Untitled (shOT3eEF) (Autodesk Fusion 360 design; units mm, degrees)
Autodesk Fusion 360 part; units mm, degrees
sketch "Sketch1" plane through (0, 0, 0) normal (0, 0, 1) x (1, 0, 0)
  line L0 (-6.3093, 9.3027) -> (-6.3093, 5.8366)
  line L1 (-6.7958, 5.7043) -> (-9.574, 5.7043)
  line L2 (-9.574, 5.7043) -> (-9.574, 5.8366)
  line L3 (-6.7958, 5.7043) -> (-6.7958, 5.8366)
  line L4 (-6.7958, 5.8366) -> (-6.3093, 5.8366)
  line L5 (-10.0605, 5.8366) -> (-10.0605, 9.3024)
  line L6 (-9.574, 5.8366) -> (-10.0605, 5.8366)
  line L7 (-10.0605, 9.3024) -> (-9.574, 9.3024)
  line L8 (-9.574, 9.3024) -> (-9.574, 9.4347)
  line L9 (-9.574, 9.4347) -> (-6.7958, 9.4347)
  line L10 (-6.7958, 9.4347) -> (-6.7958, 9.3024)
  line L11 (-6.7958, 9.3024) -> (-6.3093, 9.3024)
  line L12 (-6.7958, 5.8366) -> (-6.3093, 5.8366)
  line L13 (-6.7958, 5.7043) -> (-9.574, 5.7043)
  line L14 (-9.574, 5.8366) -> (-10.0605, 5.8366)
  line L15 (-9.574, 5.7043) -> (-9.574, 5.8366)
  line L16 (-6.7958, 5.7043) -> (-6.7958, 5.8366)
  line L17 (-6.3093, 9.3027) -> (-6.3093, 5.8366)
  line L18 (-6.7958, 9.4347) -> (-6.7958, 9.3024)
  line L19 (-9.574, 9.3024) -> (-9.574, 9.4347)
  line L20 (-10.0605, 5.8366) -> (-10.0605, 9.3024)
  line L21 (-6.7958, 9.3024) -> (-6.3093, 9.3024)
  line L22 (-9.574, 9.4347) -> (-6.7958, 9.4347)
  line L23 (-10.0605, 9.3024) -> (-9.574, 9.3024)
  line L24 (-1.5571, 5.7043) -> (-1.5571, 5.8366)
  line L25 (-4.3352, 5.7043) -> (-4.3352, 5.8366)
  line L26 (-1.5571, 9.4347) -> (-1.5571, 9.3024)
  line L27 (-4.3352, 9.3024) -> (-4.3352, 9.4347)
  line L28 (-4.3352, 5.8366) -> (-4.8218, 5.8366)
  line L29 (-4.8218, 9.3024) -> (-4.3352, 9.3024)
  line L30 (-1.5571, 5.8366) -> (-1.0705, 5.8366)
  line L31 (-4.8218, 9.3024) -> (-4.3352, 9.3024)
  line L32 (-1.5571, 5.7043) -> (-4.3352, 5.7043)
  line L33 (-1.5571, 5.8366) -> (-1.0705, 5.8366)
  line L34 (-1.5571, 5.7043) -> (-1.5571, 5.8366)
  line L35 (-4.3352, 5.8366) -> (-4.8218, 5.8366)
  line L36 (-4.3352, 9.4347) -> (-1.5571, 9.4347)
  line L37 (-1.5571, 5.7043) -> (-4.3352, 5.7043)
  line L38 (-4.3352, 9.4347) -> (-1.5571, 9.4347)
  line L39 (-1.5571, 9.3024) -> (-1.0705, 9.3024)
  line L40 (-1.5571, 9.3024) -> (-1.0705, 9.3024)
  line L41 (-4.3352, 9.3024) -> (-4.3352, 9.4347)
  line L42 (-1.5571, 9.4347) -> (-1.5571, 9.3024)
  line L43 (-4.3352, 5.7043) -> (-4.3352, 5.8366)
  line L44 (-1.0705, 9.3027) -> (-1.0705, 5.8366)
  line L45 (-1.0705, 9.3027) -> (-1.0705, 5.8366)
  line L46 (-4.8218, 5.8366) -> (-4.8218, 9.3024)
  line L47 (-4.8218, 5.8366) -> (-4.8218, 9.3024)
  line L48 (3.6817, 5.7043) -> (3.6817, 5.8366)
  line L49 (0.9035, 5.7043) -> (0.9035, 5.8366)
  line L50 (3.6817, 9.4347) -> (3.6817, 9.3024)
  line L51 (0.9035, 9.3024) -> (0.9035, 9.4347)
  line L52 (0.9035, 5.8366) -> (0.417, 5.8366)
  line L53 (0.417, 9.3024) -> (0.9035, 9.3024)
  line L54 (3.6817, 5.8366) -> (4.1682, 5.8366)
  line L55 (0.417, 9.3024) -> (0.9035, 9.3024)
  line L56 (3.6817, 5.7043) -> (0.9035, 5.7043)
  line L57 (3.6817, 5.8366) -> (4.1682, 5.8366)
  line L58 (3.6817, 5.7043) -> (3.6817, 5.8366)
  line L59 (0.9035, 5.8366) -> (0.417, 5.8366)
  line L60 (0.9035, 9.4347) -> (3.6817, 9.4347)
  line L61 (3.6817, 5.7043) -> (0.9035, 5.7043)
  line L62 (0.9035, 9.4347) -> (3.6817, 9.4347)
  line L63 (3.6817, 9.3024) -> (4.1682, 9.3024)
  line L64 (3.6817, 9.3024) -> (4.1682, 9.3024)
  line L65 (0.9035, 9.3024) -> (0.9035, 9.4347)
  line L66 (3.6817, 9.4347) -> (3.6817, 9.3024)
  line L67 (0.9035, 5.7043) -> (0.9035, 5.8366)
  line L68 (4.1682, 9.3027) -> (4.1682, 5.8366)
  line L69 (4.1682, 9.3027) -> (4.1682, 5.8366)
  line L70 (0.417, 5.8366) -> (0.417, 9.3024)
  line L71 (0.417, 5.8366) -> (0.417, 9.3024)
  line L72 (8.9204, 5.7043) -> (8.9204, 5.8366)
  line L73 (6.1423, 5.7043) -> (6.1423, 5.8366)
  line L74 (8.9204, 9.4347) -> (8.9204, 9.3024)
  line L75 (6.1423, 9.3024) -> (6.1423, 9.4347)
  line L76 (6.1423, 5.8366) -> (5.6557, 5.8366)
  line L77 (5.6557, 9.3024) -> (6.1423, 9.3024)
  line L78 (8.9204, 5.8366) -> (9.407, 5.8366)
  line L79 (5.6557, 9.3024) -> (6.1423, 9.3024)
  line L80 (8.9204, 5.7043) -> (6.1423, 5.7043)
  line L81 (8.9204, 5.8366) -> (9.407, 5.8366)
  line L82 (8.9204, 5.7043) -> (8.9204, 5.8366)
  line L83 (6.1423, 5.8366) -> (5.6557, 5.8366)
  line L84 (6.1423, 9.4347) -> (8.9204, 9.4347)
  line L85 (8.9204, 5.7043) -> (6.1423, 5.7043)
  line L86 (6.1423, 9.4347) -> (8.9204, 9.4347)
  line L87 (8.9204, 9.3024) -> (9.407, 9.3024)
  line L88 (8.9204, 9.3024) -> (9.407, 9.3024)
  line L89 (6.1423, 9.3024) -> (6.1423, 9.4347)
  line L90 (8.9204, 9.4347) -> (8.9204, 9.3024)
  line L91 (6.1423, 5.7043) -> (6.1423, 5.8366)
  line L92 (9.407, 9.3027) -> (9.407, 5.8366)
  line L93 (9.407, 9.3027) -> (9.407, 5.8366)
  line L94 (5.6557, 5.8366) -> (5.6557, 9.3024)
  line L95 (5.6557, 5.8366) -> (5.6557, 9.3024)
  line L96 (-9.574, 4.0636) -> (-9.574, 4.1959)
  line L97 (5.6557, 0.5981) -> (5.6557, 4.0636)
  line L98 (4.1682, 4.0636) -> (4.1682, 0.5981)
  line L99 (5.6557, 0.5981) -> (5.6557, 4.0636)
  line L100 (-9.574, 4.0636) -> (-9.574, 4.1959)
  line L101 (8.9204, 0.4658) -> (8.9204, 0.5981)
  line L102 (-10.0605, 4.0636) -> (-9.574, 4.0636)
  line L103 (-10.0605, 4.0636) -> (-9.574, 4.0636)
  line L104 (9.407, 4.0636) -> (9.407, 0.5981)
  line L105 (-4.3352, 4.0636) -> (-4.3352, 4.1959)
  line L106 (9.407, 4.0636) -> (9.407, 0.5981)
  line L107 (8.9204, 4.0636) -> (9.407, 4.0636)
  line L108 (8.9204, 4.1959) -> (8.9204, 4.0636)
  line L109 (8.9204, 4.1959) -> (8.9204, 4.0636)
  line L110 (8.9204, 0.5981) -> (9.407, 0.5981)
  line L111 (8.9204, 0.5981) -> (9.407, 0.5981)
  line L112 (5.6557, 4.0636) -> (6.1423, 4.0636)
  line L113 (8.9204, 0.4658) -> (8.9204, 0.5981)
  line L114 (6.1423, 4.0636) -> (6.1423, 4.1959)
  line L115 (6.1423, 4.0636) -> (6.1423, 4.1959)
  line L116 (5.6557, 4.0636) -> (6.1423, 4.0636)
  line L117 (-6.7958, 4.1959) -> (-6.7958, 4.0636)
  line L118 (6.1423, 4.1959) -> (8.9204, 4.1959)
  line L119 (-1.5571, 4.1959) -> (-1.5571, 4.0636)
  line L120 (-6.7958, 4.0636) -> (-6.3093, 4.0636)
  line L121 (6.1423, 0.5981) -> (5.6557, 0.5981)
  line L122 (0.9035, 4.1959) -> (3.6817, 4.1959)
  line L123 (-6.7958, 0.4658) -> (-9.574, 0.4658)
  line L124 (-6.7958, 4.0636) -> (-6.3093, 4.0636)
  line L125 (-6.7958, 0.4658) -> (-9.574, 0.4658)
  line L126 (-9.574, 0.5981) -> (-10.0605, 0.5981)
  line L127 (-9.574, 0.5981) -> (-10.0605, 0.5981)
  line L128 (0.9035, 4.1959) -> (3.6817, 4.1959)
  line L129 (6.1423, 0.4658) -> (6.1423, 0.5981)
  line L130 (0.417, 4.0636) -> (0.9035, 4.0636)
  line L131 (-6.3093, 4.0636) -> (-6.3093, 0.5981)
  line L132 (6.1423, 0.4658) -> (6.1423, 0.5981)
  line L133 (-1.0705, 4.0636) -> (-1.0705, 0.5981)
  line L134 (-9.574, 4.1959) -> (-6.7958, 4.1959)
  line L135 (-9.574, 0.4658) -> (-9.574, 0.5981)
  line L136 (-4.3352, 4.1959) -> (-1.5571, 4.1959)
  line L137 (6.1423, 0.5981) -> (5.6557, 0.5981)
  line L138 (-9.574, 4.1959) -> (-6.7958, 4.1959)
  line L139 (-4.3352, 4.1959) -> (-1.5571, 4.1959)
  line L140 (-6.7958, 4.1959) -> (-6.7958, 4.0636)
  line L141 (0.9035, 4.0636) -> (0.9035, 4.1959)
  line L142 (-1.0705, 4.0636) -> (-1.0705, 0.5981)
  line L143 (-9.574, 0.4658) -> (-9.574, 0.5981)
  line L144 (-4.3352, 4.0636) -> (-4.3352, 4.1959)
  line L145 (-4.8218, 4.0636) -> (-4.3352, 4.0636)
  line L146 (4.1682, 4.0636) -> (4.1682, 0.5981)
  line L147 (-4.8218, 4.0636) -> (-4.3352, 4.0636)
  line L148 (3.6817, 4.0636) -> (4.1682, 4.0636)
  line L149 (8.9204, 0.4658) -> (6.1423, 0.4658)
  line L150 (3.6817, 4.1959) -> (3.6817, 4.0636)
  line L151 (-1.5571, 4.1959) -> (-1.5571, 4.0636)
  line L152 (3.6817, 4.1959) -> (3.6817, 4.0636)
  line L153 (3.6817, 4.0636) -> (4.1682, 4.0636)
  line L154 (-1.5571, 4.0636) -> (-1.0705, 4.0636)
  line L155 (-1.5571, 4.0636) -> (-1.0705, 4.0636)
  line L156 (6.1423, 4.1959) -> (8.9204, 4.1959)
  line L157 (8.9204, 0.4658) -> (6.1423, 0.4658)
  line L158 (0.9035, 0.5981) -> (0.417, 0.5981)
  line L159 (-6.7958, 0.5981) -> (-6.3093, 0.5981)
  line L160 (-1.5571, 0.5981) -> (-1.0705, 0.5981)
  line L161 (3.6817, 0.4658) -> (3.6817, 0.5981)
  line L162 (0.417, 0.5981) -> (0.417, 4.0636)
  line L163 (3.6817, 0.4658) -> (0.9035, 0.4658)
  line L164 (-6.7958, 0.4658) -> (-6.7958, 0.5981)
  line L165 (0.9035, 0.5981) -> (0.417, 0.5981)
  line L166 (0.9035, 0.4658) -> (0.9035, 0.5981)
  line L167 (3.6817, 0.5981) -> (4.1682, 0.5981)
  line L168 (-4.8218, 0.5981) -> (-4.8218, 4.0636)
  line L169 (-6.7958, 0.4658) -> (-6.7958, 0.5981)
  line L170 (3.6817, 0.5981) -> (4.1682, 0.5981)
  line L171 (3.6817, 0.4658) -> (3.6817, 0.5981)
  line L172 (-4.3352, 0.4658) -> (-4.3352, 0.5981)
  line L173 (-4.3352, 0.5981) -> (-4.8218, 0.5981)
  line L174 (-6.7958, 0.5981) -> (-6.3093, 0.5981)
  line L175 (-1.5571, 0.5981) -> (-1.0705, 0.5981)
  line L176 (-1.5571, 0.4658) -> (-1.5571, 0.5981)
  line L177 (0.417, 0.5981) -> (0.417, 4.0636)
  line L178 (-1.5571, 0.4658) -> (-4.3352, 0.4658)
  line L179 (-4.3352, 0.5981) -> (-4.8218, 0.5981)
  line L180 (-4.8218, 0.5981) -> (-4.8218, 4.0636)
  line L181 (0.9035, 0.4658) -> (0.9035, 0.5981)
  line L182 (3.6817, 0.4658) -> (0.9035, 0.4658)
  line L183 (-1.5571, 0.4658) -> (-1.5571, 0.5981)
  line L184 (-1.5571, 0.4658) -> (-4.3352, 0.4658)
  line L185 (-4.3352, 0.4658) -> (-4.3352, 0.5981)
  line L186 (-10.0605, 0.5981) -> (-10.0605, 4.0636)
  line L187 (0.9035, 4.0636) -> (0.9035, 4.1959)
  line L188 (-6.3093, 4.0636) -> (-6.3093, 0.5981)
  line L189 (-10.0605, 0.5981) -> (-10.0605, 4.0636)
  line L190 (0.417, 4.0636) -> (0.9035, 4.0636)
  line L191 (8.9204, 4.0636) -> (9.407, 4.0636)
  line L192 (-4.8218, -6.4136) -> (-4.3352, -6.4136)
  line L193 (-9.574, -6.4136) -> (-9.574, -6.2813)
  line L194 (-10.0605, -6.4136) -> (-9.574, -6.4136)
  line L195 (6.1423, -6.2813) -> (8.9204, -6.2813)
  line L196 (6.1423, -6.2813) -> (8.9204, -6.2813)
  line L197 (3.6817, -1.0428) -> (3.6817, -1.1751)
  line L198 (3.6817, -1.0428) -> (3.6817, -1.1751)
  line L199 (6.1423, -6.4136) -> (6.1423, -6.2813)
  line L200 (5.6557, -6.4136) -> (6.1423, -6.4136)
  line L201 (5.6557, -6.4136) -> (6.1423, -6.4136)
  line L202 (6.1423, -6.4136) -> (6.1423, -6.2813)
  line L203 (3.6817, -1.1751) -> (4.1682, -1.1751)
  line L204 (3.6817, -1.1751) -> (4.1682, -1.1751)
  line L205 (3.6817, -9.8796) -> (4.1682, -9.8796)
  line L206 (4.1682, -6.4136) -> (4.1682, -9.8796)
  line L207 (4.1682, -6.4136) -> (4.1682, -9.8796)
  line L208 (-6.3093, -6.4136) -> (-6.3093, -9.8796)
  line L209 (5.6557, -9.8796) -> (5.6557, -6.4136)
  line L210 (5.6557, -9.8796) -> (5.6557, -6.4136)
  line L211 (-6.3093, -6.4136) -> (-6.3093, -9.8796)
  line L212 (-4.3352, -1.0428) -> (-1.5571, -1.0428)
  line L213 (-4.3352, -1.0428) -> (-1.5571, -1.0428)
  line L214 (3.6817, -10.0119) -> (3.6817, -9.8796)
  line L215 (8.9204, -9.8796) -> (9.407, -9.8796)
  line L216 (3.6817, -10.0119) -> (0.9035, -10.0119)
  line L217 (-6.7958, -10.0119) -> (-9.574, -10.0119)
  line L218 (-9.574, -1.1751) -> (-9.574, -1.0428)
  line L219 (-10.0605, -9.8796) -> (-10.0605, -6.4136)
  line L220 (-10.0605, -1.1751) -> (-9.574, -1.1751)
  line L221 (-10.0605, -1.1751) -> (-9.574, -1.1751)
  line L222 (-9.574, -1.0428) -> (-6.7958, -1.0428)
  line L223 (-10.0605, -9.8796) -> (-10.0605, -6.4136)
  line L224 (-9.574, -1.0428) -> (-6.7958, -1.0428)
  line L225 (3.6817, -9.8796) -> (4.1682, -9.8796)
  line L226 (3.6817, -10.0119) -> (0.9035, -10.0119)
  line L227 (3.6817, -10.0119) -> (3.6817, -9.8796)
  line L228 (0.417, -4.6406) -> (0.417, -1.1751)
  line L229 (3.6817, -6.4136) -> (4.1682, -6.4136)
  line L230 (0.9035, -1.1751) -> (0.9035, -1.0428)
  line L231 (6.1423, -9.8796) -> (5.6557, -9.8796)
  line L232 (5.6557, -4.6406) -> (5.6557, -1.1751)
  line L233 (9.407, -1.1751) -> (9.407, -4.6406)
  line L234 (9.407, -6.4136) -> (9.407, -9.8796)
  line L235 (9.407, -6.4136) -> (9.407, -9.8796)
  line L236 (0.9035, -1.1751) -> (0.9035, -1.0428)
  line L237 (8.9204, -10.0119) -> (8.9204, -9.8796)
  line L238 (-1.5571, -6.2813) -> (-1.5571, -6.4136)
  line L239 (-1.5571, -6.2813) -> (-1.5571, -6.4136)
  line L240 (-10.0605, -4.6406) -> (-10.0605, -1.1751)
  line L241 (0.417, -4.6406) -> (0.417, -1.1751)
  line L242 (-1.5571, -6.4136) -> (-1.0705, -6.4136)
  line L243 (9.407, -1.1751) -> (9.407, -4.6406)
  line L244 (4.1682, -1.1751) -> (4.1682, -4.6406)
  line L245 (3.6817, -6.2813) -> (3.6817, -6.4136)
  line L246 (0.417, -1.1751) -> (0.9035, -1.1751)
  line L247 (5.6557, -4.6406) -> (5.6557, -1.1751)
  line L248 (-1.5571, -4.7729) -> (-1.5571, -4.6406)
  line L249 (3.6817, -6.2813) -> (3.6817, -6.4136)
  line L250 (8.9204, -10.0119) -> (8.9204, -9.8796)
  line L251 (6.1423, -10.0119) -> (6.1423, -9.8796)
  line L252 (8.9204, -10.0119) -> (6.1423, -10.0119)
  line L253 (-1.5571, -6.4136) -> (-1.0705, -6.4136)
  line L254 (-4.8218, -4.6406) -> (-4.8218, -1.1751)
  line L255 (-1.0705, -1.1751) -> (-1.0705, -4.6406)
  line L256 (-6.3093, -1.1751) -> (-6.3093, -4.6406)
  line L257 (-6.7958, -4.7729) -> (-6.7958, -4.6406)
  line L258 (-1.0705, -1.1751) -> (-1.0705, -4.6406)
  line L259 (0.9035, -1.0428) -> (3.6817, -1.0428)
  line L260 (-6.7958, -6.4136) -> (-6.3093, -6.4136)
  line L261 (4.1682, -1.1751) -> (4.1682, -4.6406)
  line L262 (6.1423, -9.8796) -> (5.6557, -9.8796)
  line L263 (-1.5571, -4.6406) -> (-1.0705, -4.6406)
  line L264 (-1.5571, -4.7729) -> (-1.5571, -4.6406)
  line L265 (8.9204, -10.0119) -> (6.1423, -10.0119)
  line L266 (-6.7958, -6.2813) -> (-6.7958, -6.4136)
  line L267 (-6.3093, -1.1751) -> (-6.3093, -4.6406)
  line L268 (3.6817, -6.4136) -> (4.1682, -6.4136)
  line L269 (-10.0605, -4.6406) -> (-10.0605, -1.1751)
  line L270 (-6.7958, -6.2813) -> (-6.7958, -6.4136)
  line L271 (6.1423, -10.0119) -> (6.1423, -9.8796)
  line L272 (0.9035, -1.0428) -> (3.6817, -1.0428)
  line L273 (8.9204, -9.8796) -> (9.407, -9.8796)
  line L274 (-6.7958, -6.4136) -> (-6.3093, -6.4136)
  line L275 (0.417, -1.1751) -> (0.9035, -1.1751)
  line L276 (-4.8218, -4.6406) -> (-4.8218, -1.1751)
  line L277 (6.1423, -1.1751) -> (6.1423, -1.0428)
  line L278 (8.9204, -1.0428) -> (8.9204, -1.1751)
  line L279 (8.9204, -1.0428) -> (8.9204, -1.1751)
  line L280 (-10.0605, -6.4136) -> (-9.574, -6.4136)
  line L281 (8.9204, -1.1751) -> (9.407, -1.1751)
  line L282 (8.9204, -1.1751) -> (9.407, -1.1751)
  line L283 (-4.3352, -6.2813) -> (-1.5571, -6.2813)
  line L284 (6.1423, -1.1751) -> (6.1423, -1.0428)
  line L285 (-4.3352, -6.2813) -> (-1.5571, -6.2813)
  line L286 (5.6557, -1.1751) -> (6.1423, -1.1751)
  line L287 (5.6557, -1.1751) -> (6.1423, -1.1751)
  line L288 (6.1423, -1.0428) -> (8.9204, -1.0428)
  line L289 (3.6817, -4.7729) -> (3.6817, -4.6406)
  line L290 (-1.5571, -4.7729) -> (-4.3352, -4.7729)
  line L291 (-9.574, -6.2813) -> (-6.7958, -6.2813)
  line L292 (8.9204, -4.7729) -> (6.1423, -4.7729)
  line L293 (8.9204, -4.7729) -> (6.1423, -4.7729)
  line L294 (-6.7958, -4.7729) -> (-9.574, -4.7729)
  line L295 (3.6817, -4.6406) -> (4.1682, -4.6406)
  line L296 (6.1423, -1.0428) -> (8.9204, -1.0428)
  line L297 (3.6817, -4.6406) -> (4.1682, -4.6406)
  line L298 (3.6817, -4.7729) -> (3.6817, -4.6406)
  line L299 (-9.574, -6.2813) -> (-6.7958, -6.2813)
  line L300 (-9.574, -6.4136) -> (-9.574, -6.2813)
  line L301 (-9.574, -4.7729) -> (-9.574, -4.6406)
  line L302 (-9.574, -4.7729) -> (-9.574, -4.6406)
  line L303 (-6.7958, -4.7729) -> (-9.574, -4.7729)
  line L304 (-6.7958, -4.7729) -> (-6.7958, -4.6406)
  line L305 (-6.7958, -4.6406) -> (-6.3093, -4.6406)
  line L306 (-1.5571, -4.7729) -> (-4.3352, -4.7729)
  line L307 (0.417, -9.8796) -> (0.417, -6.4136)
  line L308 (-1.5571, -9.8796) -> (-1.0705, -9.8796)
  line L309 (0.9035, -4.6406) -> (0.417, -4.6406)
  line L310 (-6.7958, -10.0119) -> (-6.7958, -9.8796)
  line L311 (-4.3352, -10.0119) -> (-4.3352, -9.8796)
  line L312 (-9.574, -10.0119) -> (-9.574, -9.8796)
  line L313 (-4.3352, -4.6406) -> (-4.8218, -4.6406)
  line L314 (-1.5571, -10.0119) -> (-1.5571, -9.8796)
  line L315 (-9.574, -4.6406) -> (-10.0605, -4.6406)
  line L316 (-1.5571, -1.1751) -> (-1.0705, -1.1751)
  line L317 (-1.5571, -1.1751) -> (-1.0705, -1.1751)
  line L318 (-4.8218, -1.1751) -> (-4.3352, -1.1751)
  line L319 (-4.3352, -1.1751) -> (-4.3352, -1.0428)
  line L320 (0.417, -6.4136) -> (0.9035, -6.4136)
  line L321 (-9.574, -1.1751) -> (-9.574, -1.0428)
  line L322 (-6.7958, -1.0428) -> (-6.7958, -1.1751)
  line L323 (-6.7958, -1.1751) -> (-6.3093, -1.1751)
  line L324 (0.9035, -6.2813) -> (3.6817, -6.2813)
  line L325 (-1.5571, -1.0428) -> (-1.5571, -1.1751)
  line L326 (0.9035, -6.2813) -> (3.6817, -6.2813)
  line L327 (0.9035, -4.6406) -> (0.417, -4.6406)
  line L328 (3.6817, -4.7729) -> (0.9035, -4.7729)
  line L329 (0.9035, -6.4136) -> (0.9035, -6.2813)
  line L330 (-4.8218, -9.8796) -> (-4.8218, -6.4136)
  line L331 (-4.8218, -9.8796) -> (-4.8218, -6.4136)
  line L332 (-1.5571, -10.0119) -> (-4.3352, -10.0119)
  line L333 (-6.7958, -10.0119) -> (-9.574, -10.0119)
  line L334 (0.9035, -4.7729) -> (0.9035, -4.6406)
  line L335 (-4.3352, -10.0119) -> (-4.3352, -9.8796)
  line L336 (-9.574, -4.6406) -> (-10.0605, -4.6406)
  line L337 (-9.574, -9.8796) -> (-10.0605, -9.8796)
  line L338 (-6.7958, -10.0119) -> (-6.7958, -9.8796)
  line L339 (-6.7958, -9.8796) -> (-6.3093, -9.8796)
  line L340 (0.417, -6.4136) -> (0.9035, -6.4136)
  line L341 (-1.5571, -10.0119) -> (-1.5571, -9.8796)
  line L342 (-1.5571, -10.0119) -> (-4.3352, -10.0119)
  line L343 (-6.7958, -4.6406) -> (-6.3093, -4.6406)
  line L344 (-9.574, -10.0119) -> (-9.574, -9.8796)
  line L345 (3.6817, -4.7729) -> (0.9035, -4.7729)
  line L346 (-4.3352, -1.1751) -> (-4.3352, -1.0428)
  line L347 (0.9035, -10.0119) -> (0.9035, -9.8796)
  line L348 (0.9035, -10.0119) -> (0.9035, -9.8796)
  line L349 (-4.3352, -9.8796) -> (-4.8218, -9.8796)
  line L350 (-1.5571, -9.8796) -> (-1.0705, -9.8796)
  line L351 (-1.5571, -4.6406) -> (-1.0705, -4.6406)
  line L352 (0.9035, -4.7729) -> (0.9035, -4.6406)
  line L353 (-4.3352, -9.8796) -> (-4.8218, -9.8796)
  line L354 (-9.574, -9.8796) -> (-10.0605, -9.8796)
  line L355 (0.417, -9.8796) -> (0.417, -6.4136)
  line L356 (-4.8218, -1.1751) -> (-4.3352, -1.1751)
  line L357 (-1.5571, -1.0428) -> (-1.5571, -1.1751)
  line L358 (-4.3352, -4.6406) -> (-4.8218, -4.6406)
  line L359 (-6.7958, -1.1751) -> (-6.3093, -1.1751)
  line L360 (-6.7958, -1.0428) -> (-6.7958, -1.1751)
  line L361 (-1.0705, -6.4136) -> (-1.0705, -9.8796)
  line L362 (0.9035, -6.4136) -> (0.9035, -6.2813)
  line L363 (-1.0705, -6.4136) -> (-1.0705, -9.8796)
  line L364 (0.9035, -9.8796) -> (0.417, -9.8796)
  line L365 (-6.7958, -9.8796) -> (-6.3093, -9.8796)
  line L366 (0.9035, -9.8796) -> (0.417, -9.8796)
  line L367 (8.9204, -6.4136) -> (9.407, -6.4136)
  line L368 (8.9204, -6.4136) -> (9.407, -6.4136)
  line L369 (8.9204, -6.2813) -> (8.9204, -6.4136)
  line L370 (-4.3352, -4.7729) -> (-4.3352, -4.6406)
  line L371 (-4.3352, -6.4136) -> (-4.3352, -6.2813)
  line L372 (8.9204, -4.6406) -> (9.407, -4.6406)
  line L373 (6.1423, -4.6406) -> (5.6557, -4.6406)
  line L374 (6.1423, -4.7729) -> (6.1423, -4.6406)
  line L375 (6.1423, -4.6406) -> (5.6557, -4.6406)
  line L376 (8.9204, -4.7729) -> (8.9204, -4.6406)
  line L377 (-4.8218, -6.4136) -> (-4.3352, -6.4136)
  line L378 (-4.3352, -6.4136) -> (-4.3352, -6.2813)
  line L379 (-4.3352, -4.7729) -> (-4.3352, -4.6406)
  line L380 (6.1423, -4.7729) -> (6.1423, -4.6406)
  line L381 (8.9204, -4.7729) -> (8.9204, -4.6406)
  line L382 (8.9204, -4.6406) -> (9.407, -4.6406)
  line L383 (8.9204, -6.2813) -> (8.9204, -6.4136)
  spline S0 degree 3 poles (-2.6218, 10.1099) (-1.6216, 10.4449) (-0.5395, 10.4449) (0.4606, 10.1099) knots 0 0 0 0 1 1 1 1
  spline S1 degree 3 poles (0.4606, 10.1099) (0.4606, 9.8649) (0.6591, 9.6665) (0.9038, 9.6665) knots 0 0 0 0 1 1 1 1
  spline S2 degree 3 poles (0.9038, 9.6665) (1.1485, 9.6665) (1.347, 9.8649) (1.347, 10.1099) knots 0 0 0 0 1 1 1 1
  spline S3 degree 3 poles (1.347, 10.1099) (1.3443, 10.1967) (1.3631, 10.2827) (1.4007, 10.361) knots 0 0 0 0 1 1 1 1
  line L384 (1.4007, 10.361) -> (10.2931, 10.357)
  line L385 (10.2931, 10.357) -> (10.2931, -10.8057)
  line L386 (10.2931, -10.8057) -> (-10.9469, -10.8057)
  line L387 (-10.9469, -10.8057) -> (-10.9469, 10.3607)
  line L388 (-10.9469, 10.3607) -> (-3.5626, 10.3607)
  spline S4 degree 3 poles (-3.5626, 10.3607) (-3.5222, 10.2835) (-3.5034, 10.1967) (-3.5081, 10.1099) knots 0 0 0 0 1 1 1 1
  spline S5 degree 3 poles (-3.5081, 10.1099) (-3.5081, 9.8649) (-3.31, 9.6665) (-3.065, 9.6665) knots 0 0 0 0 1 1 1 1
  spline S6 degree 3 poles (-3.065, 9.6665) (-2.8202, 9.6665) (-2.6218, 9.8649) (-2.6218, 10.1099) knots 0 0 0 0 1 1 1 1
extrude "Extrude1" add sketch "Sketch1" along normal blind 2
scale "Scale1" factors (3.766431, 3.792781, 1) about (-6.3093, 4.0636, 2) bodies 1
sketch "Sketch2" plane through (0, 0, 2) normal (0, 0, 1) x (1, 0, 0)
  line L0 (-8.1419, 10.7881) -> (-8.1419, 10.2864)
  line L1 (-8.1419, 10.2864) -> (-18.6055, 10.2864)
  line L2 (-18.6055, 10.2864) -> (-18.6055, 10.7881)
  line L3 (-18.6055, 10.7881) -> (-20.4381, 10.7881)
  line L4 (-20.4381, 10.7881) -> (-20.4381, 23.9331)
  line L5 (-20.4381, 23.9331) -> (-18.6055, 23.9331)
  line L6 (-18.6055, 23.9331) -> (-18.6055, 24.4348)
  line L7 (-18.6055, 24.4348) -> (-8.1419, 24.4348)
  line L8 (-8.1419, 24.4348) -> (-8.1419, 23.9331)
  line L9 (-8.1419, 23.9331) -> (-6.3093, 23.9331)
  line L10 (-6.3093, 23.9331) -> (-6.3093, 10.7881)
  line L11 (-6.3093, 10.7881) -> (-8.1419, 10.7881)
  line L12 (51.0523, 10.7881) -> (51.0523, 10.2864)
  line L13 (51.0523, 10.2864) -> (40.5887, 10.2864)
  line L14 (40.5887, 10.2864) -> (40.5887, 10.7881)
  line L15 (40.5887, 10.7881) -> (38.756, 10.7881)
  line L16 (38.756, 10.7881) -> (38.756, 23.9331)
  line L17 (38.756, 23.9331) -> (40.5887, 23.9331)
  line L18 (40.5887, 23.9331) -> (40.5887, 24.4348)
  line L19 (40.5887, 24.4348) -> (51.0523, 24.4348)
  line L20 (51.0523, 24.4348) -> (51.0523, 23.9331)
  line L21 (51.0523, 23.9331) -> (52.8849, 23.9331)
  line L22 (52.8849, 23.9331) -> (52.8849, 10.7881)
  line L23 (52.8849, 10.7881) -> (51.0523, 10.7881)
  line L24 (11.5895, -9.0803) -> (11.5895, -9.582)
  line L25 (11.5895, -9.582) -> (1.1259, -9.582)
  line L26 (1.1259, -9.582) -> (1.1259, -9.0803)
  line L27 (1.1259, -9.0803) -> (-0.7067, -9.0803)
  line L28 (-0.7067, -9.0803) -> (-0.7067, 4.0636)
  line L29 (-0.7067, 4.0636) -> (1.1259, 4.0636)
  line L30 (1.1259, 4.0636) -> (1.1259, 4.5654)
  line L31 (1.1259, 4.5654) -> (11.5895, 4.5654)
  line L32 (11.5895, 4.5654) -> (11.5895, 4.0636)
  line L33 (11.5895, 4.0636) -> (13.4221, 4.0636)
  line L34 (13.4221, 4.0636) -> (13.4221, -9.0803)
  line L35 (13.4221, -9.0803) -> (11.5895, -9.0803)
  line L36 (11.5895, 10.7881) -> (11.5895, 10.2864)
  line L37 (11.5895, 10.2864) -> (1.1259, 10.2864)
  line L38 (1.1259, 10.2864) -> (1.1259, 10.7881)
  line L39 (1.1259, 10.7881) -> (-0.7067, 10.7881)
  line L40 (-0.7067, 10.7881) -> (-0.7067, 23.9331)
  line L41 (-0.7067, 23.9331) -> (1.1259, 23.9331)
  line L42 (1.1259, 23.9331) -> (1.1259, 24.4348)
  line L43 (1.1259, 24.4348) -> (11.5895, 24.4348)
  line L44 (11.5895, 24.4348) -> (11.5895, 23.9331)
  line L45 (11.5895, 23.9331) -> (13.4221, 23.9331)
  line L46 (13.4221, 23.9331) -> (13.4221, 10.7881)
  line L47 (13.4221, 10.7881) -> (11.5895, 10.7881)
  line L48 (-8.1419, -28.9497) -> (-8.1419, -29.4515)
  line L49 (-8.1419, -29.4515) -> (-18.6055, -29.4515)
  line L50 (-18.6055, -29.4515) -> (-18.6055, -28.9497)
  line L51 (-18.6055, -28.9497) -> (-20.4381, -28.9497)
  line L52 (-20.4381, -28.9497) -> (-20.4381, -15.8058)
  line L53 (-20.4381, -15.8058) -> (-18.6055, -15.8058)
  line L54 (-18.6055, -15.8058) -> (-18.6055, -15.304)
  line L55 (-18.6055, -15.304) -> (-8.1419, -15.304)
  line L56 (-8.1419, -15.304) -> (-8.1419, -15.8058)
  line L57 (-8.1419, -15.8058) -> (-6.3093, -15.8058)
  line L58 (-6.3093, -15.8058) -> (-6.3093, -28.9497)
  line L59 (-6.3093, -28.9497) -> (-8.1419, -28.9497)
  line L60 (51.0523, -48.8201) -> (51.0523, -49.3219)
  line L61 (51.0523, -49.3219) -> (40.5887, -49.3219)
  line L62 (40.5887, -49.3219) -> (40.5887, -48.8201)
  line L63 (40.5887, -48.8201) -> (38.756, -48.8201)
  line L64 (38.756, -48.8201) -> (38.756, -35.6742)
  line L65 (38.756, -35.6742) -> (40.5887, -35.6742)
  line L66 (40.5887, -35.6742) -> (40.5887, -35.1725)
  line L67 (40.5887, -35.1725) -> (51.0523, -35.1725)
  line L68 (51.0523, -35.1725) -> (51.0523, -35.6742)
  line L69 (51.0523, -35.6742) -> (52.8849, -35.6742)
  line L70 (52.8849, -35.6742) -> (52.8849, -48.8201)
  line L71 (52.8849, -48.8201) -> (51.0523, -48.8201)
  line L72 (31.3209, -9.0803) -> (31.3209, -9.582)
  line L73 (31.3209, -9.582) -> (20.8573, -9.582)
  line L74 (20.8573, -9.582) -> (20.8573, -9.0803)
  line L75 (20.8573, -9.0803) -> (19.0246, -9.0803)
  line L76 (19.0246, -9.0803) -> (19.0246, 4.0636)
  line L77 (19.0246, 4.0636) -> (20.8573, 4.0636)
  line L78 (20.8573, 4.0636) -> (20.8573, 4.5654)
  line L79 (20.8573, 4.5654) -> (31.3209, 4.5654)
  line L80 (31.3209, 4.5654) -> (31.3209, 4.0636)
  line L81 (31.3209, 4.0636) -> (33.1535, 4.0636)
  line L82 (33.1535, 4.0636) -> (33.1535, -9.0803)
  line L83 (33.1535, -9.0803) -> (31.3209, -9.0803)
  line L84 (31.3209, -28.9497) -> (31.3209, -29.4515)
  line L85 (31.3209, -29.4515) -> (20.8573, -29.4515)
  line L86 (20.8573, -29.4515) -> (20.8573, -28.9497)
  line L87 (20.8573, -28.9497) -> (19.0246, -28.9497)
  line L88 (19.0246, -28.9497) -> (19.0246, -15.8058)
  line L89 (19.0246, -15.8058) -> (20.8573, -15.8058)
  line L90 (20.8573, -15.8058) -> (20.8573, -15.304)
  line L91 (20.8573, -15.304) -> (31.3209, -15.304)
  line L92 (31.3209, -15.304) -> (31.3209, -15.8058)
  line L93 (31.3209, -15.8058) -> (33.1535, -15.8058)
  line L94 (33.1535, -15.8058) -> (33.1535, -28.9497)
  line L95 (33.1535, -28.9497) -> (31.3209, -28.9497)
  line L96 (-8.1419, -48.8201) -> (-8.1419, -49.3219)
  line L97 (-8.1419, -49.3219) -> (-18.6055, -49.3219)
  line L98 (-18.6055, -49.3219) -> (-18.6055, -48.8201)
  line L99 (-18.6055, -48.8201) -> (-20.4381, -48.8201)
  line L100 (-20.4381, -48.8201) -> (-20.4381, -35.6742)
  line L101 (-20.4381, -35.6742) -> (-18.6055, -35.6742)
  line L102 (-18.6055, -35.6742) -> (-18.6055, -35.1725)
  line L103 (-18.6055, -35.1725) -> (-8.1419, -35.1725)
  line L104 (-8.1419, -35.1725) -> (-8.1419, -35.6742)
  line L105 (-8.1419, -35.6742) -> (-6.3093, -35.6742)
  line L106 (-6.3093, -35.6742) -> (-6.3093, -48.8201)
  line L107 (-6.3093, -48.8201) -> (-8.1419, -48.8201)
  line L108 (31.3209, -48.8201) -> (31.3209, -49.3219)
  line L109 (31.3209, -49.3219) -> (20.8573, -49.3219)
  line L110 (20.8573, -49.3219) -> (20.8573, -48.8201)
  line L111 (20.8573, -48.8201) -> (19.0246, -48.8201)
  line L112 (19.0246, -48.8201) -> (19.0246, -35.6742)
  line L113 (19.0246, -35.6742) -> (20.8573, -35.6742)
  line L114 (20.8573, -35.6742) -> (20.8573, -35.1725)
  line L115 (20.8573, -35.1725) -> (31.3209, -35.1725)
  line L116 (31.3209, -35.1725) -> (31.3209, -35.6742)
  line L117 (31.3209, -35.6742) -> (33.1535, -35.6742)
  line L118 (33.1535, -35.6742) -> (33.1535, -48.8201)
  line L119 (33.1535, -48.8201) -> (31.3209, -48.8201)
  line L120 (51.0523, -9.0803) -> (51.0523, -9.582)
  line L121 (51.0523, -9.582) -> (40.5887, -9.582)
  line L122 (40.5887, -9.582) -> (40.5887, -9.0803)
  line L123 (40.5887, -9.0803) -> (38.756, -9.0803)
  line L124 (38.756, -9.0803) -> (38.756, 4.0636)
  line L125 (38.756, 4.0636) -> (40.5887, 4.0636)
  line L126 (40.5887, 4.0636) -> (40.5887, 4.5654)
  line L127 (40.5887, 4.5654) -> (51.0523, 4.5654)
  line L128 (51.0523, 4.5654) -> (51.0523, 4.0636)
  line L129 (51.0523, 4.0636) -> (52.8849, 4.0636)
  line L130 (52.8849, 4.0636) -> (52.8849, -9.0803)
  line L131 (52.8849, -9.0803) -> (51.0523, -9.0803)
  line L132 (11.5895, -48.8201) -> (11.5895, -49.3219)
  line L133 (11.5895, -49.3219) -> (1.1259, -49.3219)
  line L134 (1.1259, -49.3219) -> (1.1259, -48.8201)
  line L135 (1.1259, -48.8201) -> (-0.7067, -48.8201)
  line L136 (-0.7067, -48.8201) -> (-0.7067, -35.6742)
  line L137 (-0.7067, -35.6742) -> (1.1259, -35.6742)
  line L138 (1.1259, -35.6742) -> (1.1259, -35.1725)
  line L139 (1.1259, -35.1725) -> (11.5895, -35.1725)
  line L140 (11.5895, -35.1725) -> (11.5895, -35.6742)
  line L141 (11.5895, -35.6742) -> (13.4221, -35.6742)
  line L142 (13.4221, -35.6742) -> (13.4221, -48.8201)
  line L143 (13.4221, -48.8201) -> (11.5895, -48.8201)
  line L144 (11.5895, -28.9497) -> (11.5895, -29.4515)
  line L145 (11.5895, -29.4515) -> (1.1259, -29.4515)
  line L146 (1.1259, -29.4515) -> (1.1259, -28.9497)
  line L147 (1.1259, -28.9497) -> (-0.7067, -28.9497)
  line L148 (-0.7067, -28.9497) -> (-0.7067, -15.8058)
  line L149 (-0.7067, -15.8058) -> (1.1259, -15.8058)
  line L150 (1.1259, -15.8058) -> (1.1259, -15.304)
  line L151 (1.1259, -15.304) -> (11.5895, -15.304)
  line L152 (11.5895, -15.304) -> (11.5895, -15.8058)
  line L153 (11.5895, -15.8058) -> (13.4221, -15.8058)
  line L154 (13.4221, -15.8058) -> (13.4221, -28.9497)
  line L155 (13.4221, -28.9497) -> (11.5895, -28.9497)
  line L156 (51.0523, -28.9497) -> (51.0523, -29.4515)
  line L157 (51.0523, -29.4515) -> (40.5887, -29.4515)
  line L158 (40.5887, -29.4515) -> (40.5887, -28.9497)
  line L159 (40.5887, -28.9497) -> (38.756, -28.9497)
  line L160 (38.756, -28.9497) -> (38.756, -15.8058)
  line L161 (38.756, -15.8058) -> (40.5887, -15.8058)
  line L162 (40.5887, -15.8058) -> (40.5887, -15.304)
  line L163 (40.5887, -15.304) -> (51.0523, -15.304)
  line L164 (51.0523, -15.304) -> (51.0523, -15.8058)
  line L165 (51.0523, -15.8058) -> (52.8849, -15.8058)
  line L166 (52.8849, -15.8058) -> (52.8849, -28.9497)
  line L167 (52.8849, -28.9497) -> (51.0523, -28.9497)
  line L168 (31.3209, 10.7881) -> (31.3209, 10.2864)
  line L169 (31.3209, 10.2864) -> (20.8573, 10.2864)
  line L170 (20.8573, 10.2864) -> (20.8573, 10.7881)
  line L171 (20.8573, 10.7881) -> (19.0246, 10.7881)
  line L172 (19.0246, 10.7881) -> (19.0246, 23.9331)
  line L173 (19.0246, 23.9331) -> (20.8573, 23.9331)
  line L174 (20.8573, 23.9331) -> (20.8573, 24.4348)
  line L175 (20.8573, 24.4348) -> (31.3209, 24.4348)
  line L176 (31.3209, 24.4348) -> (31.3209, 23.9331)
  line L177 (31.3209, 23.9331) -> (33.1535, 23.9331)
  line L178 (33.1535, 23.9331) -> (33.1535, 10.7881)
  line L179 (33.1535, 10.7881) -> (31.3209, 10.7881)
  line L180 (-8.1419, -9.0803) -> (-8.1419, -9.582)
  line L181 (-8.1419, -9.582) -> (-18.6055, -9.582)
  line L182 (-18.6055, -9.582) -> (-18.6055, -9.0803)
  line L183 (-18.6055, -9.0803) -> (-20.4381, -9.0803)
  line L184 (-20.4381, -9.0803) -> (-20.4381, 4.0636)
  line L185 (-20.4381, 4.0636) -> (-18.6055, 4.0636)
  line L186 (-18.6055, 4.0636) -> (-18.6055, 4.5654)
  line L187 (-18.6055, 4.5654) -> (-8.1419, 4.5654)
  line L188 (-8.1419, 4.5654) -> (-8.1419, 4.0636)
  line L189 (-8.1419, 4.0636) -> (-6.3093, 4.0636)
  line L190 (-6.3093, 4.0636) -> (-6.3093, -9.0803)
  line L191 (-6.3093, -9.0803) -> (-8.1419, -9.0803)
  spline S0 degree 3 poles (5.9102, 25.3139) (4.9874, 25.3139) (4.241, 26.0665) (4.241, 26.9958) knots -1 -1 -1 -1 0 0 0 0
  spline S1 degree 3 poles (4.241, 26.9958) (4.2589, 27.3249) (4.1882, 27.6541) (4.0357, 27.9471) knots -1 -1 -1 -1 0 0 0 0
  line L192 (4.0357, 27.9471) -> (-23.7766, 27.9471)
  line L193 (-23.7766, 27.9471) -> (-23.7766, -52.3324)
  line L194 (-23.7766, -52.3324) -> (56.2223, -52.3324)
  line L195 (56.2223, -52.3324) -> (56.2223, 27.933)
  line L196 (56.2223, 27.933) -> (22.7297, 27.9481)
  spline S2 degree 3 poles (22.7297, 27.9481) (22.5882, 27.6511) (22.5174, 27.3249) (22.5274, 26.9958) knots -1 -1 -1 -1 0 0 0 0
  spline S3 degree 3 poles (22.5274, 26.9958) (22.5274, 26.0665) (21.78, 25.3139) (20.8582, 25.3139) knots -1 -1 -1 -1 0 0 0 0
  spline S4 degree 3 poles (20.8582, 25.3139) (19.9365, 25.3139) (19.1891, 26.0665) (19.1891, 26.9958) knots -1 -1 -1 -1 0 0 0 0
  spline S5 degree 3 poles (19.1891, 26.9958) (15.4222, 28.2662) (11.3463, 28.2662) (7.5794, 26.9958) knots -1 -1 -1 -1 0 0 0 0
  spline S6 degree 3 poles (7.5794, 26.9958) (7.5794, 26.0665) (6.832, 25.3139) (5.9102, 25.3139) knots -1 -1 -1 -1 0 0 0 0
